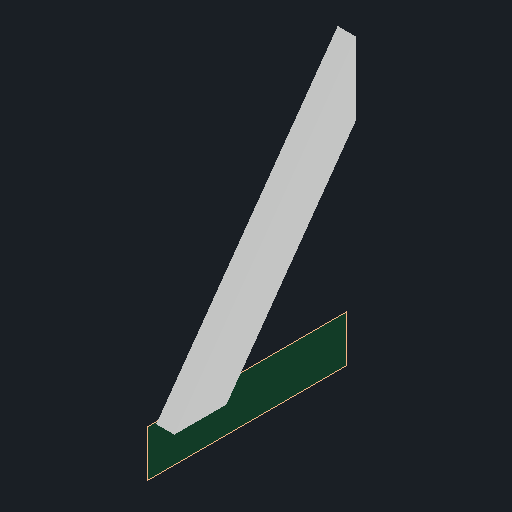
# Autodesk Inventor part: Top of Head Diagonals 2
Saved by Autodesk Inventor 2027 (Build 310192000, 192)
## iProperties
Created: 2026-10-17
Part Number: Top of Head Diagonals 2
Material: Generic
Document SubType Name: Modeling
Designer: lucas
Density: 1 g/cm^3
Appearance: Default
Author: lucas
Autodesk Inventor part; units mm, degrees
ref_plane "YZ Plane" through (0, 0, 0) normal (1, 0, 0) x (0, 1, 0)
ref_plane "XZ Plane" through (0, 0, 0) normal (0, 1, 0) x (-1, 0, 0)
ref_plane "XY Plane" through (0, 0, 0) normal (0, 0, 1) x (1, 0, 0)
ref_plane "Work Plane1" through (-838.2, -533.4, 190.5) normal (-1, 0, 0) x (0, 0, 1)
sketch "Sketch1" plane through (-838.2, -533.4, 190.5) normal (-1, 0, 0) x (0, 0, 1)
  line L0 (-190.5, 577.85) -> (190.5, 44.45)
  line L1 (-190.5, 424.9007) -> (81.2505, 44.45)
  line L2 (-190.5, 577.85) -> (-190.5, 424.9007)
  line L3 (81.2505, 44.45) -> (190.5, 44.45)
  point P0 (-190.5, 533.4)
  dimension "d0" = 88.9
  constraints: 8 end point, 1 horizontal, 1 parallel, 1 vertical, 2 other
  measures "d0" distance between parallel lines of L0 L1
extrude "Extrusion1" add sketch "Sketch1" against normal blind 38.1
body "Solid1"
